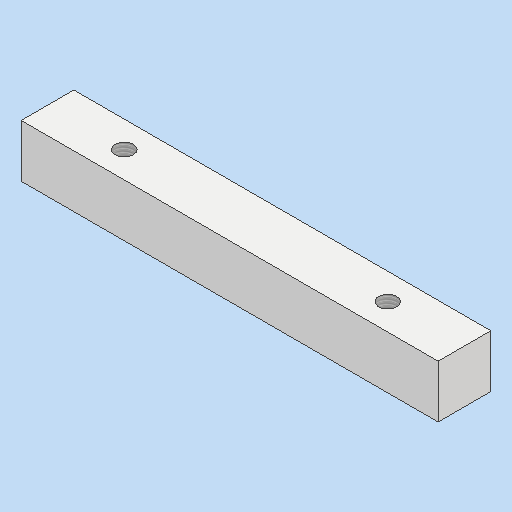
# Autodesk Inventor part: MM0948AN100_G01_135
Saved by Autodesk Inventor 2023.3 (Build 273359000, 359)
## iProperties
RuleStatus: InUse
Created: 2023-03-30
Part Number: MM0948AN100_G01_135
Material: Kst - Pa 6 (weiss)
Description: =<RBPARTNOTITLE2>
Document SubType Name: Modeling
Designer: FH/Wi
Mass: 15.228 g
Surface Area: 51.0601 cm^2
Volume: 13.3579 cm^3
Density: 1.14 g/cm^3
Appearance: weiss AnP
AnP_Kategorie: 1
AnP_Material: =<Material>
MaxAbmaße: 12 x 12 x 95 (FM)
AnP_TemplVers: 20200821
RBDOCUMENTTYPE: DRF
RBDOCUMENTVERSION: 00
RBDRAWINGMAINSCALE: 1:1
RBDRAWINGMISSINGSPEC: --
RBDRAWINGVOLUME: --
RBDSV1: 0850
RBGBEDGESIN1: +0,5
RBGBEDGESIN2: +0,2
RBGBEDGESOUT1: -0,3
RBGBEDGESOUT2: -0,1
RBMATERIAL: =<Material>
RBMATMEETS: --
RBMATNO: =<Part Number>
RBPARTMADEOF: 12 x 12 x 95 (FM)
RBPARTNO: SIEHE MNR
RBPARTNOTITLE1: manufactured part
RBPARTNOTITLE2: Anfertigungsteil
RBPARTSAFETYINDICATOR: --
RBSURFACE: --
RBSURFACE2: --
RBZEDGESNORM: ISO13715:2002-06
RBZGENDIMCLASS: m
RBZGENDIMNORM: ISO 2768-1:1989-11
RBZGENGEOCLASS: H
RBZGENGEONORM: ISO 2768-2:1989-11
RBZSURFACENORM: ISO13D2:2002-02
RBZTOLERANCENORM: ISO 14405-1:2010-12
Author: FH/Wi
Keywords: =<RBPARTMADEOF>
Comments: =<RBSURFACE2>
Revision Number: 01
Autodesk Inventor part; units mm, degrees
ref_plane "YZ Plane" through (0, 0, 0) normal (1, 0, 0) x (0, 1, 0)
ref_plane "XZ Plane" through (0, 0, 0) normal (0, 1, 0) x (-1, 0, 0)
ref_plane "XY Plane" through (0, 0, 0) normal (0, 0, 1) x (1, 0, 0)
sketch "Skizze1" plane through (0, 0, 0) normal (0, 0, 1) x (1, 0, 0)
  line L0 (-47.5, 6) -> (47.5, 6)
  line L1 (47.5, 6) -> (47.5, -6)
  line L2 (47.5, -6) -> (-47.5, -6)
  line L3 (-47.5, -6) -> (-47.5, 6)
  point P0 (0, 0)
  point P1 (47.5, 0)
  point P2 (0, 6)
  dimension "d0" = 12
  dimension "d1" = 95
  constraints: 8 end point, 2 midpoint, 2 parallel, 1 horizontal, 1 horizontal alignment, 1 perpendicular, 1 vertical alignment
  measures "d0" distance of L2.end L0.start
  measures "d1" distance of L0.start L0.end
extrude "Extrusion1" add sketch "Skizze1" along normal blind 12
sketch "Skizze2" plane through (0, 0, 12) normal (0, 0, 1) x (1, 0, 0)
  line L0 (-30, 0) -> (30, 0)
  point P0 (0, 0)
  point P1 (0, 0)
  dimension "d11" = 60
  constraints: 2 end point, 1 coincident, 1 horizontal, 1 midpoint
  measures "d11" distance of L0.start L0.end
hole "Bohrung1" at (-30, 0, 12) at (30, 0, 12) direction (0, 0, -1) diameter 4.134 end through all thread size "M5x0.8" designation "M5" class "6H" standard "ISO Metric profile"
